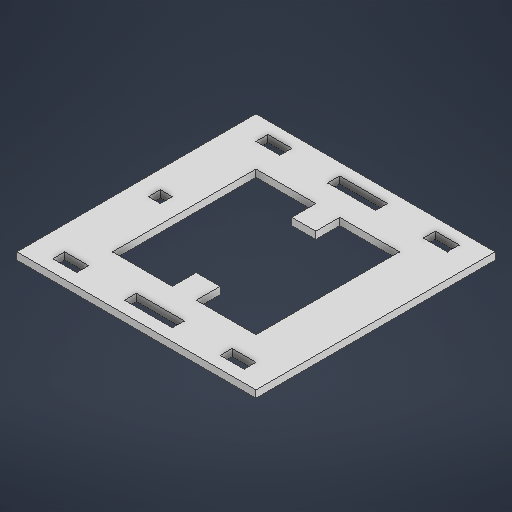
# Autodesk Inventor part: Medio
Saved by Autodesk Inventor 2025.2 (Build 292293000, 293)
## iProperties
Created: 2025-06-04
Part Number: Medio
Material: Genérico
Document SubType Name: Modeling
Designer: Niko
Density: 1 g/cm^3
Appearance: Valor por defecto
Author: Niko
Autodesk Inventor part; units mm, degrees
ref_plane "YZ Plane" through (0, 0, 0) normal (1, 0, 0) x (0, 1, 0)
ref_plane "XZ Plane" through (0, 0, 0) normal (0, 1, 0) x (-1, 0, 0)
ref_plane "XY Plane" through (0, 0, 0) normal (0, 0, 1) x (1, 0, 0)
sketch "Boceto1" plane through (0, 0, 0) normal (0, 1, 0) x (-1, 0, 0)
  line L0 (50, 50) -> (-50, 50)
  line L1 (-50, 50) -> (-50, -50)
  line L2 (-50, -50) -> (50, -50)
  line L3 (50, -50) -> (50, 50)
  line L4 (50, 30) -> (50, 50)
  line L5 (-30, 30) -> (-30, -30)
  line L6 (30, -30) -> (30, 30)
  line L7 (30, 30) -> (5, 30)
  line L8 (-5, 30) -> (-5, 20)
  line L9 (-5, 20) -> (5, 20)
  line L10 (5, 20) -> (5, 30)
  line L11 (-5, -30) -> (-5, -20)
  line L12 (-5, -20) -> (5, -20)
  line L13 (5, -20) -> (5, -30)
  line L14 (-30, -30) -> (-5, -30)
  line L15 (5, -30) -> (30, -30)
  line L16 (30, 30) -> (5, 30)
  line L17 (-5, 30) -> (-30, 30)
  line L18 (50, 50) -> (50, 45)
  line L19 (40, 45) -> (30, 45)
  line L20 (30, 45) -> (30, 40)
  line L21 (30, 40) -> (40, 40)
  line L22 (40, 40) -> (40, 45)
  line L23 (0, 45) -> (10, 45)
  line L24 (10, 45) -> (10, 40)
  line L25 (10, 40) -> (0, 40)
  line L26 (-40, 45) -> (-30, 45)
  line L27 (-30, 45) -> (-30, 40)
  line L28 (-30, 40) -> (-40, 40)
  line L29 (-40, 40) -> (-40, 45)
  line L30 (0, 45) -> (-10, 45)
  line L31 (-10, 45) -> (-10, 40)
  line L32 (-10, 40) -> (0, 40)
  line L33 (40, -45) -> (30, -45)
  line L34 (30, -45) -> (30, -40)
  line L35 (30, -40) -> (40, -40)
  line L36 (40, -40) -> (40, -45)
  line L37 (0, -45) -> (10, -45)
  line L38 (10, -45) -> (10, -40)
  line L39 (10, -40) -> (0, -40)
  line L40 (-30, -45) -> (-30, -40)
  line L41 (-30, -40) -> (-40, -40)
  line L42 (-40, -40) -> (-40, -45)
  line L43 (-40, -45) -> (-30, -45)
  line L44 (-10, -45) -> (-10, -40)
  line L45 (0, -45) -> (-10, -45)
  line L46 (-10, -40) -> (0, -40)
  line L47 (40, -2.5) -> (42.5, -2.5)
  line L48 (42.5, -2.5) -> (37.5, -2.5)
  line L49 (37.5, -2.5) -> (37.5, 2.5)
  line L50 (37.5, 2.5) -> (42.5, 2.5)
  line L51 (42.5, 2.5) -> (42.5, -2.5)
  point P0 (0, 0)
  constraints: 104 end point, 14 parallel, 11 point on line, 7 horizontal, 6 perpendicular
extrude "Extrusión2" add sketch "Boceto1" along normal blind 3
